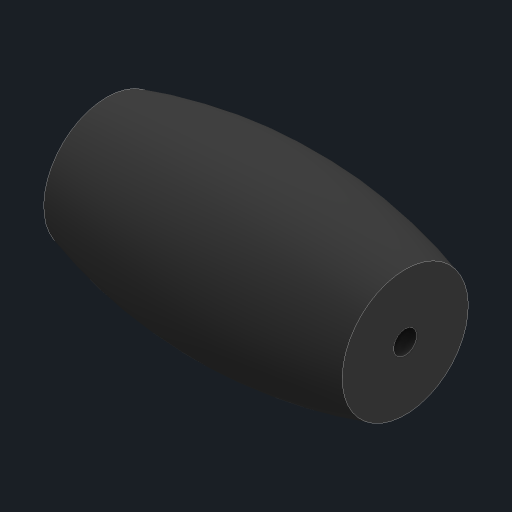
# Autodesk Inventor part: Rolete
Saved by Autodesk Inventor 2024.3 (Build 283343000, 343)
## iProperties
Created: 2025-01-03
Part Number: Rolete
Material: ABS plástico
Document SubType Name: Modeling
Designer: Cliente
Density: 0.907306 g/cm^3
Appearance: Borracha - Preta
Mass: 8.169 g
Surface Area: 26.6561 cm^2
Volume: 9.04755 cm^3
Author: Cliente
Autodesk Inventor part; units mm, degrees
ref_plane "YZ Plane" through (0, 0, 0) normal (1, 0, 0) x (0, 1, 0)
ref_plane "XZ Plane" through (0, 0, 0) normal (0, 1, 0) x (-1, 0, 0)
ref_plane "XY Plane" through (0, 0, 0) normal (0, 0, 1) x (1, 0, 0)
sketch "Esboço1" plane through (0, 0, 0) normal (0, 0, 1) x (1, 0, 0)
  circle A0 centre (0, 0) radius 60
  line L0 (0, 0) -> (0, 50)
  line L1 (-17.5, 50) -> (17.5, 50)
  line L2 (-17.5, 50) -> (-17.5, 57.3912)
  line L3 (17.5, 50) -> (17.5, 57.3912)
  line L4 (-17.5, 51.35) -> (17.5, 51.35)
  dimension "d0" = 120
  dimension "d1" = 50
  dimension "d2" = 35
  dimension "d3" = 1.35
  constraints: 10 end point, 2 parallel, 2 point on circle, 2 point on line, 2 vertical, 1 centre point, 1 coincident, 1 horizontal, 1 midpoint
  measures "d0" diameter of A0
  measures "d1" distance of L0.end L0.start
  measures "d2" distance of L1.start L1.end
  measures "d3" distance between parallel lines of L1 L4
revolve "Revolução1" add sketch "Esboço1" angle 360 about axis through (-17.5, 50, 0) along (1, 0, 0) contours L3 L4 L2 A0
